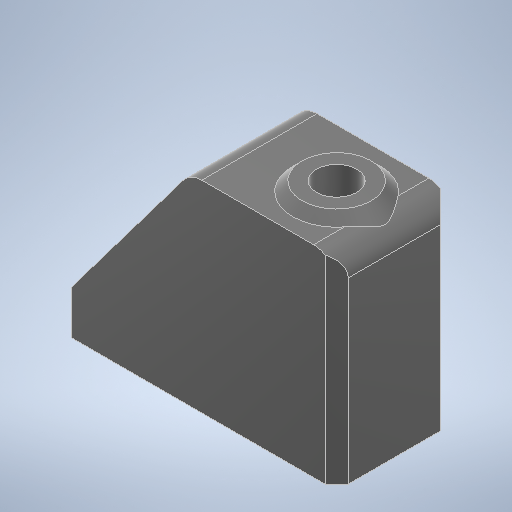
# Autodesk Inventor part: 3D_XT30-fix3
Saved by Autodesk Inventor 2025.3 (Build 293356030, 356C)
## iProperties
Created: 2025-09-08
Part Number: 3D_XT30-fix3
Material: 一般
Document SubType Name: Modeling
Designer: ibuki_ono
Density: 1 g/cm^3
Appearance: 滑らか - 黒
Author: ibuki_ono
## iProperties of the stored document 3D_XT30-fix3_3D プリント.ipt
Created: 2025-09-08
Part Number: 3D_XT30-fix3_3D プリント
Material: 一般
Document SubType Name: Modeling
Designer: ibuki_ono
Density: 1 g/cm^3
Appearance: 既定
Author: ibuki_ono
Autodesk Inventor part; units mm, degrees
ref_plane "YZ Plane" through (0, 0, 0) normal (1, 0, 0) x (0, 1, 0)
ref_plane "XZ Plane" through (0, 0, 0) normal (0, 1, 0) x (-1, 0, 0)
ref_plane "XY Plane" through (0, 0, 0) normal (0, 0, 1) x (1, 0, 0)
sketch "スケッチ1" plane through (0, 0, 0) normal (0, 0, 1) x (1, 0, 0)
  line L0 (-12, -1.25) -> (12, -1.25)
  line L1 (12, -1.25) -> (12, 1.25)
  line L2 (12, 1.25) -> (-12, 1.25)
  line L3 (-12, 1.25) -> (-12, -1.25)
  line L4 (-12, -1.25) -> (12, 1.25) construction
  line L5 (12, -1.25) -> (-12, 1.25) construction
  line L6 (-0.7, 1.25) -> (6.1, 1.25)
  line L7 (6.1, 1.25) -> (6.1, 16.25)
  line L8 (6.1, 16.25) -> (-0.7, 16.25)
  line L9 (-0.7, 16.25) -> (-0.7, 1.25)
  line L10 (-0.7, 16.25) -> (-12, 1.25)
  line L11 (12, 1.25) -> (6.1, 1.25)
  line L12 (6.1, 1.25) -> (6.1, 16.25)
  line L13 (6.1, 16.25) -> (12, 16.25)
  line L14 (12, 16.25) -> (12, 1.25)
  point P0 (0, 0)
  dimension "d0" = 24
  dimension "d1" = 2.5
  dimension "d2" = 6.8
  dimension "d3" = 15
  dimension "d4" = 11.3
  constraints: 30 end point, 6 parallel, 3 horizontal, 3 perpendicular, 2 midpoint, 1 point on line
  measures "d0" distance of L2.end L1.end
  measures "d1" distance of L1.end L0.end
  measures "d2" distance of L8.end L7.end
  measures "d3" distance of L7.end L6.end
  measures "d4" distance between parallel lines of L3 L9
extrude "押し出し1" add sketch "スケッチ1" along normal mid plane 10
sketch "スケッチ2" plane through (0, 0, -5) normal (0, 0, -1) x (-1, 0, 0)
  line L0 (12, -1.25) -> (12, 1.25) projected
  line L1 (-12, -1.25) -> (12, -1.25) projected
  line L2 (0.7, 16.25) -> (-12, 16.25) projected
  line L3 (0.7, 14.95) -> (-1.1, 14.95)
  line L4 (-1.1, 14.95) -> (-1.1, -1.25)
  line L5 (-1.1, -1.25) -> (0.7, -1.25)
  line L6 (0.7, -1.25) -> (0.7, 14.95)
  point P0 (0, 0)
  point P1 (-6.1, 16.25)
  point P2 (-1.1, -1.25)
  dimension "d7" = 1.8
  dimension "d8" = 16.2
  dimension "d9" = 11.3
  constraints: 8 end point, 2 parallel, 1 collinear, 1 horizontal, 1 perpendicular
  measures "d7" distance of L5.end L4.end
  measures "d8" distance of L4.end L3.end
  measures "d9" distance between parallel lines of L0 L6
extrude "押し出し2" cut sketch "スケッチ2" against normal blind 4
sketch "スケッチ3" plane through (-0.7, 16.25, 5) normal (0, 1, 0) x (1, 0, 0)
  line L0 (-11.3, 0) -> (-11.3, 10) projected
  line L1 (12.7, 5) -> (-11.3, 5) construction
  line L2 (12.7, 10) -> (12.7, 0) projected
  point P0 (0.7, 5)
  point P1 (7.7, 5)
  point P2 (-6.3, 5)
  dimension "d13" = 5
  dimension "d21" = 5
  constraints: 4 midpoint, 2 end point, 2 point on line
  measures "d13" distance from line of L0 point (-6.3, 5)
  measures "d21" distance from line of L2 point (7.7, 5)
hole "穴1" at (7, 16.25, 0) at (-7, 16.25, 0) direction (0, -1, 0) diameter 3.5 end through all
sketch "スケッチ4" plane through (-0.7, 16.25, 5) normal (0, 1, 0) x (1, 0, 0)
  circle A0 centre (-6.3, 5) radius 1.75 projected
  circle A1 centre (-6.3, 5) radius 3
  point P0 (0.7, 5)
  dimension "d22" = 6
  constraints: 1 centre point, 1 coincident
  measures "d22" diameter of A1
extrude "押し出し3" cut sketch "スケッチ4" against normal blind 15
sketch "スケッチ5" plane through (-0.7, 16.25, 5) normal (0, 1, 0) x (1, 0, 0)
  circle A0 centre (7.7, 5) radius 1.75 projected
  circle A1 centre (7.7, 5) radius 3
  point P0 (0.7, 5)
  dimension "d25" = 6
  constraints: 1 centre point, 1 coincident
  measures "d25" diameter of A1
extrude "押し出し4" add sketch "スケッチ5" along normal blind 0.8
chamfer "面取り1" distance 0.8 angle 45 1 edges at (4, 16.25, 0)
chamfer "面取り2" distance 1 angle 45 4 edges at (12, 7.5, 5) (12, 7.5, -5) (-12, 0, 5) (-12, 0, -5)
fillet "フィレット1" radius 2 3 edges at (-0.7, 16.25, 0) (12, 16.25, 0) (-12, 1.25, 0)
equation "\"d13\" = d12"
equation "\"d12\" = 5"
